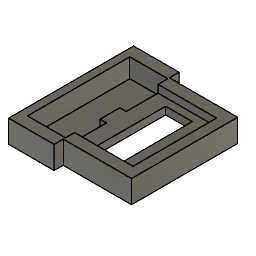
dynamometer_final (Autodesk Fusion 360 design; units mm, degrees)
part number: 2026-03-10-14-24-55-489
part number: 2026-03-10-14-33-02-371
part number: 2026-03-10-16-50-15-956
Autodesk Fusion 360 part; units mm, degrees
sketch "Sketch1" plane through (0, 0, 0) normal (0, 0, 1) x (1, 0, 0) in component "base_v1"
  line L0 (20, 20) -> (170, 20)
  line L1 (170, 20) -> (170, 160)
  line L2 (170, 160) -> (20, 160)
  line L3 (20, 160) -> (20, 20)
  line L4 (20, 30) -> (160, 30)
  line L5 (160, 30) -> (160, 150)
  line L6 (160, 150) -> (20, 150)
  line L7 (79.2096, 30) -> (79.2096, 150)
  line L8 (193.3788, 275.1806) -> (208.3788, 275.1806)
  line L9 (208.3788, 275.1806) -> (208.3788, 355.1806)
  line L10 (208.3788, 355.1806) -> (193.3788, 355.1806)
  line L11 (193.3788, 355.1806) -> (193.3788, 275.1806)
  line L12 (25, 175) -> (25, 320)
  line L13 (79.2096, 30) -> (67.601, 30)
  line L14 (67.601, 30) -> (67.601, 74.5756)
  line L15 (67.601, 74.5756) -> (79.2096, 74.5756)
  line L16 (79.2096, 74.5756) -> (79.2096, 30)
  line L17 (200.8788, 355.1806) -> (200.8788, 337.1806)
  circle A0 centre (200.8788, 337.1806) radius 2.4
  circle A1 centre (200.8788, 347.1806) radius 2.4
  line L18 (200.8788, 275.1806) -> (200.8788, 293.1806)
  circle A2 centre (200.8788, 283.1806) radius 2.4
  circle A3 centre (200.8788, 293.1806) radius 2.4
  line L19 (170, 90) -> (20, 90)
  line L20 (140, 90) -> (127, 90)
  line L21 (127, 90) -> (127, 35)
  line L22 (127, 35) -> (140, 35)
  line L23 (140, 35) -> (140, 90)
  line L24 (140, 90) -> (127, 90)
  line L25 (127, 90) -> (127, 145)
  line L26 (127, 145) -> (140, 145)
  line L27 (140, 145) -> (140, 90)
  line L28 (200.8788, 337.1806) -> (216.8788, 337.1806)
  line L29 (216.8788, 347.1806) -> (200.8788, 347.1806)
  line L30 (200.8788, 347.1806) -> (200.8788, 337.1806)
  line L31 (284.8788, 287.1806) -> (271.8788, 287.1806)
  line L32 (271.8788, 287.1806) -> (271.8788, 397.1806)
  line L33 (271.8788, 397.1806) -> (284.8788, 397.1806)
  line L34 (284.8788, 397.1806) -> (284.8788, 287.1806)
  line L35 (271.8788, 287.1806) -> (236.8788, 287.1806)
  line L36 (236.8788, 287.1806) -> (236.8788, 297.1806)
  line L37 (236.8788, 297.1806) -> (271.8788, 297.1806)
  line L38 (271.8788, 297.1806) -> (271.8788, 287.1806)
  line L39 (271.8788, 397.1806) -> (236.8788, 397.1806)
  line L40 (236.8788, 397.1806) -> (236.8788, 387.1806)
  line L41 (236.8788, 387.1806) -> (271.8788, 387.1806)
  line L42 (271.8788, 387.1806) -> (271.8788, 397.1806)
  line L43 (236.8788, 287.1806) -> (216.8788, 287.1806)
  line L44 (216.8788, 287.1806) -> (216.8788, 397.1806)
  line L45 (216.8788, 397.1806) -> (236.8788, 397.1806)
  line L46 (236.8788, 397.1806) -> (236.8788, 287.1806)
  line L47 (216.8788, 337.1806) -> (216.8788, 347.1806)
  line L48 (216.8788, 355.1806) -> (208.3788, 355.1806)
  line L49 (208.3788, 355.1806) -> (208.3788, 329.1806)
  line L50 (208.3788, 329.1806) -> (216.8788, 329.1806)
  line L51 (216.8788, 329.1806) -> (216.8788, 355.1806)
  line L52 (216.8788, 287.1806) -> (306.8788, 287.1806)
  line L53 (306.8788, 287.1806) -> (306.8788, 272.1806)
  line L54 (306.8788, 272.1806) -> (216.8788, 272.1806)
  line L55 (216.8788, 272.1806) -> (216.8788, 287.1806)
  line L56 (306.8788, 287.1806) -> (293.8788, 287.1806)
  line L57 (293.8788, 287.1806) -> (293.8788, 397.1806)
  line L58 (293.8788, 397.1806) -> (306.8788, 397.1806)
  line L59 (306.8788, 397.1806) -> (306.8788, 287.1806)
  line L60 (306.8788, 397.1806) -> (216.8788, 397.1806)
  line L61 (216.8788, 397.1806) -> (216.8788, 412.1806)
  line L62 (216.8788, 412.1806) -> (306.8788, 412.1806)
  line L63 (306.8788, 412.1806) -> (306.8788, 397.1806)
  line L64 (216.8788, 275.1806) -> (156.8788, 275.1806)
  line L65 (156.8788, 275.1806) -> (156.8788, 260.1806)
  line L66 (156.8788, 260.1806) -> (216.8788, 260.1806)
  line L67 (216.8788, 260.1806) -> (216.8788, 275.1806)
  line L68 (169.827, 342.2189) -> (140, 342.2189)
  line L69 (156.8788, 275.1806) -> (166.8788, 275.1806)
  line L70 (166.8788, 275.1806) -> (166.8788, 409.9406)
  line L71 (166.8788, 409.9406) -> (156.8788, 409.9406)
  line L72 (156.8788, 409.9406) -> (156.8788, 275.1806)
  line L73 (156.8788, 409.9406) -> (216.8788, 409.9406)
  line L74 (216.8788, 409.9406) -> (216.8788, 424.9406)
  line L75 (216.8788, 424.9406) -> (156.8788, 424.9406)
  line L76 (156.8788, 424.9406) -> (156.8788, 409.9406)
  dimension "d1" = 150
  dimension "d2" = 140
  dimension "d3" = -10
  dimension "d4" = 15
  dimension "d5" = 80
  dimension "d6" = 145
  dimension "d9" = 18
  dimension "d10" = 4.8
  dimension "d11" = 4.8
  dimension "d12" = 18
  dimension "d13" = 4.8
  dimension "d14" = 4.8
  dimension "d16" = 13
  dimension "d17" = 55
  dimension "d18" = 13
  dimension "d19" = 55
  dimension "d20" = 16
  dimension "d32" = 13
  dimension "d33" = 110
  dimension "d34" = 35
  dimension "d35" = 10
  dimension "d36" = 35
  dimension "d37" = 10
  dimension "d38" = 20
  dimension "d39" = 110
  dimension "d42" = 8.5
  dimension "d43" = 26
  dimension "d44" = 90
  dimension "d45" = 15
  dimension "d46" = 13
  dimension "d47" = 110
  dimension "d48" = 90
  dimension "d49" = 15
  dimension "d50" = 60
  dimension "d51" = 15
  dimension "d52" = 10
  dimension "d53" = 134.76
  dimension "d54" = 60
  dimension "d55" = 15
  constraint horizontal L0
  constraint vertical L1
  constraint horizontal L2
  constraint vertical L3
  constraint coincident L4 L7.start
  constraint coincident L6 L7.end
  constraint perpendicular L6 L7
  constraint horizontal L8
  constraint vertical L9
  constraint horizontal L10
  constraint vertical L11
  constraint vertical L12
  constraint horizontal L13
  constraint vertical L14
  constraint horizontal L15
  constraint vertical L16
  constraint midpoint L10 L17.start
  constraint perpendicular L10 L17
  constraint coincident L17.end A0.centre
  constraint coincident L18.end A3.centre
  constraint midpoint L1 L19.start
  constraint midpoint L3 L19.end
  constraint horizontal L20
  constraint vertical L21
  constraint horizontal L22
  constraint vertical L23
  constraint coincident L19 L20.start
  constraint horizontal L24
  constraint vertical L25
  constraint horizontal L26
  constraint vertical L27
  constraint horizontal L28
  constraint horizontal L29
  constraint vertical L30
  constraint horizontal L31
  constraint vertical L32
  constraint horizontal L33
  constraint vertical L34
  constraint horizontal L35
  constraint vertical L36
  constraint horizontal L37
  constraint vertical L38
  constraint horizontal L39
  constraint vertical L40
  constraint horizontal L41
  constraint vertical L42
  constraint horizontal L43
  constraint vertical L44
  constraint horizontal L45
  constraint vertical L46
  constraint perpendicular L29 L47
  constraint horizontal L48
  constraint vertical L49
  constraint horizontal L50
  constraint vertical L51
  constraint horizontal L52
  constraint vertical L53
  constraint horizontal L54
  constraint vertical L55
  constraint horizontal L56
  constraint vertical L57
  constraint horizontal L58
  constraint vertical L59
  constraint horizontal L60
  constraint vertical L61
  constraint horizontal L62
  constraint vertical L63
  constraint horizontal L64
  constraint vertical L65
  constraint horizontal L66
  constraint vertical L67
  constraint coincident L55 L64.start
  constraint horizontal L69
  constraint vertical L70
  constraint horizontal L71
  constraint vertical L72
  constraint horizontal L73
  constraint vertical L74
  constraint horizontal L75
  constraint vertical L76
  measures "d1" distance of L0.start L0.end
  measures "d2" distance of L0.start L2.end
  measures "d4" distance of L8.start L8.end
  measures "d5" distance of L8.start L10.end
  measures "d6" distance of L12.start L12.end
  measures "d9" distance of L17.start L17.end
  measures "d10" diameter of A0
  measures "d11" diameter of A1
  measures "d12" distance of L18.end L18.start
  measures "d13" diameter of A3
  measures "d14" diameter of A2
  measures "d16" distance of L20.start L20.end
  measures "d17" distance of L20.start L22.end
  measures "d18" distance of L20.start L20.end
  measures "d19" distance of L20.start L26.end
  measures "d20" distance of L17.end L28.end
  measures "d32" distance of L31.start L31.end
  measures "d33" distance of L31.start L33.end
  measures "d34" distance of L31.end L35.end
  measures "d35" distance of L31.end L37.end
  measures "d36" distance of L32.end L39.end
  measures "d37" distance of L32.end L41.end
  measures "d38" distance of L35.end L43.end
  measures "d39" distance of L35.end L39.end
  measures "d42" distance of L48.start L9.end
  measures "d43" distance of L48.start L50.end
  measures "d44" distance of L43.end L52.end
  measures "d45" distance of L43.end L54.end
  measures "d46" distance of L52.end L56.end
  measures "d47" distance of L52.end L58.end
  measures "d48" distance of L58.end L44.end
  measures "d49" distance of L58.end L62.end
  measures "d50" distance of L64.start L64.end
  measures "d51" distance of L64.start L66.end
  measures "d52" distance of L64.end L69.end
  measures "d53" distance of L64.end L71.end
  measures "d54" distance of L71.end L73.end
  measures "d55" distance of L71.end L75.end
extrude "Extrude2" add sketch "Sketch1" along normal blind 30 contours L8 L55 L64 L65 L66 L67 L69 | L64 L68 L69 L70 L72 | L68 L70 L71 L72 L73 | L31 L35 L43 L52 L53 L54 L55 L56 L67 | L61 L71 L73 L74 L75 L76 | L33 L39 L45 L58 L60 L61 L62 L63 L74 | L52 L56 L57 L58 L59 L60 makes body 1 in component "base_v1"
extrude "Extrude3" add sketch "Sketch1" along normal blind 5 contours L8 L9 L10 L11 L17 A0 A1 L28 L30 L49 L64 | L10 L11 L44 L48 L61 L64 L70 L73 | L9 L44 L50 L55 L64 | L9 L10 L17 A1 L29 L49 | L9 L28 L44 L49 L50 L51 | L9 L29 L44 L48 L49 L51 | L17 A1 L29 | L17 A1 L30 | L9 L17 A0 A1 L28 L29 L30 L49 | L9 L28 L29 L44 L47 L49 L51 | L17 A1 L29 L30 | L17 A0 L28 L30 | L17 A0 L28 L30 | L18 A2 | L18 A2 | A3 bodies 1 in component "base_v1"
extrude "Extrude1" add sketch "Sketch1" along normal blind 10 from surface at 10 separate body contours L9 L28 L44 L49 L50 L51 | L9 L29 L44 L48 L49 L51 | L9 L28 L29 L44 L47 L49 L51 | L36 L40 L43 L44 L45 L46 L47 L51 L52 L60 | L32 L35 L36 L37 L38 L46 L52 | L31 L32 L33 L34 L38 L42 L52 L60 | L32 L39 L40 L41 L42 L46 L60 makes body 2 in component "pega"
component "base_v1" placed x (1, 0, 0) y (0, 1, 0) z (0, 0, 1) at (0, 0, 0)
component "pega" placed x (1, 0, 0) y (0, 1, 0) z (0, 0, 1) at (0, 0, 0)
